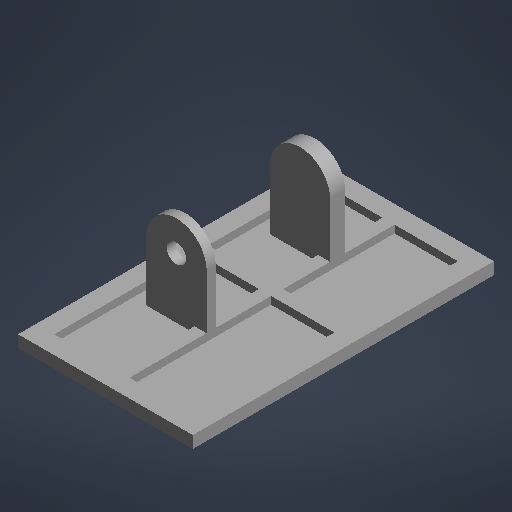
# Autodesk Inventor part: R2_pie_izq
Saved by Autodesk Inventor 2027 (Build 310192060, 192F)
## iProperties
Part Number: R2_pie_izq
Material: Genérico
Document SubType Name: Modelado
Designer: rodri
Appearance: Por defecto
Author: rodri
Autodesk Inventor part; units mm, degrees
ref_plane "Plano de trabajo1" through (0, 0, -45) normal (0, 0, 1) x (1, 0, 0)
sketch "Boceto1" plane through (0, 0, -45) normal (0, 0, 1) x (1, 0, 0)
  line L0 (3, -166) -> (61, -166)
  line L1 (61, -166) -> (61, -162)
  line L2 (61, -162) -> (3, -162)
  line L3 (3, -162) -> (3, -166)
  constraints: 8 end point, 2 parallel, 1 horizontal, 1 perpendicular
extrude "Extrusión1" add sketch "Boceto1" along normal blind 100
ref_plane "Plano de trabajo2" through (0, 0, -39) normal (0, 0, 1) x (1, 0, 0)
sketch "Boceto2" plane through (0, 0, -39) normal (0, 0, 1) x (1, 0, 0)
  line L0 (9, -164.5) -> (55, -164.5)
  line L1 (55, -164.5) -> (55, -161.9)
  line L2 (55, -161.9) -> (9, -161.9)
  line L3 (9, -161.9) -> (9, -164.5)
  constraints: 8 end point, 2 parallel, 1 horizontal, 1 perpendicular
extrude "Extrusión2" cut sketch "Boceto2" along normal blind 88
ref_plane "Plano de trabajo3" through (0, 0, -2) normal (0, 0, 1) x (1, 0, 0)
sketch "Boceto3" plane through (0, 0, -2) normal (0, 0, 1) x (1, 0, 0)
  line L0 (9, -166) -> (55, -166)
  line L1 (55, -166) -> (55, -162)
  line L2 (55, -162) -> (9, -162)
  line L3 (9, -162) -> (9, -166)
  constraints: 8 end point, 2 parallel, 1 horizontal, 1 perpendicular
extrude "Extrusión3" add sketch "Boceto3" along normal blind 4
ref_plane "Plano de trabajo4" through (0, 0, -39) normal (0, 0, 1) x (1, 0, 0)
sketch "Boceto4" plane through (0, 0, -39) normal (0, 0, 1) x (1, 0, 0)
  line L0 (30, -166) -> (34, -166)
  line L1 (34, -166) -> (34, -162)
  line L2 (34, -162) -> (30, -162)
  line L3 (30, -162) -> (30, -166)
  constraints: 8 end point, 2 parallel, 1 horizontal, 1 perpendicular
extrude "Extrusión4" add sketch "Boceto4" along normal blind 88
ref_plane "Plano de trabajo5" through (0, 0, -22.6) normal (0, 0, 1) x (1, 0, 0)
sketch "Boceto5" plane through (0, 0, -22.6) normal (0, 0, 1) x (1, 0, 0)
  line L0 (14, -164) -> (34, -164)
  line L1 (34, -164) -> (34, -144)
  line L2 (34, -144) -> (14, -144)
  line L3 (14, -144) -> (14, -164)
  constraints: 8 end point, 2 parallel, 1 horizontal, 1 perpendicular
extrude "Extrusión5" add sketch "Boceto5" along normal blind 4.99
ref_plane "Plano de trabajo6" through (0, 0, -22.6) normal (0, 0, 1) x (1, 0, 0)
sketch "Boceto6" plane through (0, 0, -22.6) normal (0, 0, 1) x (1, 0, 0)
  circle A0 centre (24, -144) radius 10
  constraints: 1 centre point
extrude "Extrusión6" add sketch "Boceto6" along normal blind 4.99
ref_plane "Plano de trabajo7" through (0, 0, 20.41) normal (0, 0, 1) x (1, 0, 0)
sketch "Boceto7" plane through (0, 0, 20.41) normal (0, 0, 1) x (1, 0, 0)
  line L0 (14, -164) -> (34, -164)
  line L1 (34, -164) -> (34, -144)
  line L2 (34, -144) -> (14, -144)
  line L3 (14, -144) -> (14, -164)
  constraints: 8 end point, 2 parallel, 1 horizontal, 1 perpendicular
extrude "Extrusión7" add sketch "Boceto7" along normal blind 3
ref_plane "Plano de trabajo8" through (0, 0, 20.41) normal (0, 0, 1) x (1, 0, 0)
sketch "Boceto8" plane through (0, 0, 20.41) normal (0, 0, 1) x (1, 0, 0)
  circle A0 centre (24, -144) radius 10
  constraints: 1 centre point
extrude "Extrusión8" add sketch "Boceto8" along normal blind 3
ref_plane "Plano de trabajo9" through (0, 0, -22.7) normal (0, 0, 1) x (1, 0, 0)
sketch "Boceto9" plane through (0, 0, -22.7) normal (0, 0, 1) x (1, 0, 0)
  circle A0 centre (24, -144) radius 4.2
  constraints: 1 centre point
extrude "Extrusión9" cut sketch "Boceto9" along normal blind 3.2
ref_plane "Plano de trabajo10" through (0, 0, 20.3) normal (0, 0, 1) x (1, 0, 0)
sketch "Boceto10" plane through (0, 0, 20.3) normal (0, 0, 1) x (1, 0, 0)
  circle A0 centre (24, -144) radius 3.15
  constraints: 1 centre point
extrude "Extrusión10" cut sketch "Boceto10" along normal blind 3.2
